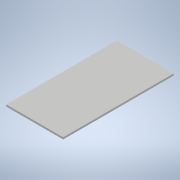
# Autodesk Inventor part: podea_scari_jos_pe_parchet
Saved by Autodesk Inventor 2022.6 (Build 266554000, 554)
## iProperties
Created: 2026-10-28
Part Number: podea_scari_jos_pe_parchet
Material: Generic
Document SubType Name: Modeling
Designer: Dragos Macovei
Density: 1 g/cm^3
Appearance: Default
Author: Dragos Macovei
Autodesk Inventor part; units mm, degrees
ref_plane "YZ Plane" through (0, 0, 0) normal (1, 0, 0) x (0, 1, 0)
ref_plane "XZ Plane" through (0, 0, 0) normal (0, 1, 0) x (-1, 0, 0)
ref_plane "XY Plane" through (0, 0, 0) normal (0, 0, 1) x (1, 0, 0)
sketch "Sketch1" plane through (0, 0, 0) normal (0, 1, 0) x (-1, 0, 0)
  line L0 (169.0508, 14.3779) -> (-390.9492, 14.3779)
  line L1 (-390.9492, 14.3779) -> (-390.9492, -1073.6221)
  line L2 (-390.9492, -1073.6221) -> (169.0508, -1073.6221)
  line L3 (169.0508, -1073.6221) -> (169.0508, 14.3779)
  point P0 (0, 0)
  dimension "d0" = 560
  dimension "d1" = 1088
  constraints: 8 end point, 2 parallel, 1 horizontal, 1 perpendicular
  measures "d0" distance of L2.end L1.end
  measures "d1" distance of L1.end L0.end
extrude "Extrusion1" add sketch "Sketch1" along normal blind 18
body "Solid1"
